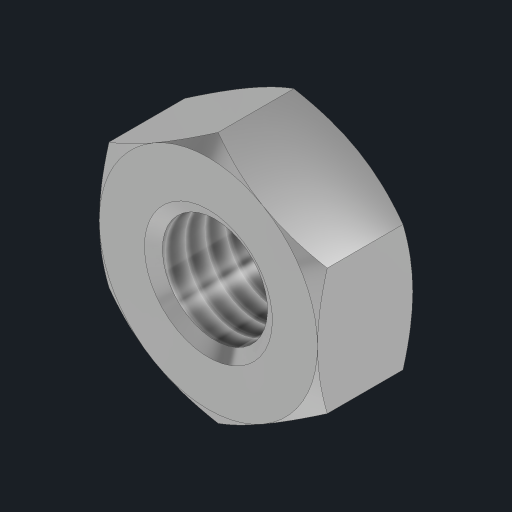
# Autodesk Inventor part: Porca Sextavada DIN 934 - M3 - 8
Saved by Autodesk Inventor 2024.3 (Build 283343000, 343)
## iProperties
Created: 2025-07-13
Part Number: Porca Sextavada DIN 934 - M3 - 8
Material: Aço inoxidável
Document SubType Name: Modeling
Designer: Cliente
Mass: 0.390793 g
Surface Area: 1.02672 cm^2
Volume: 0.0488491 cm^3
Density: 8 g/cm^3
Appearance: Aço inoxidável - Brilhoso
Author: Cliente
Autodesk Inventor part; units mm, degrees
ref_plane "YZ Plane" through (0, 0, 0) normal (1, 0, 0) x (0, 1, 0)
ref_plane "XZ Plane" through (0, 0, 0) normal (0, 1, 0) x (-1, 0, 0)
ref_plane "XY Plane" through (0, 0, 0) normal (0, 0, 1) x (1, 0, 0)
sketch "Esboço1" plane through (0, 0, 0) normal (0, 0, 1) x (1, 0, 0)
  line L0 (0, 3.1754) -> (2.75, 1.5877)
  line L1 (2.75, 1.5877) -> (2.75, -1.5877)
  line L2 (2.75, -1.5877) -> (0, -3.1754)
  line L3 (0, -3.1754) -> (-2.75, -1.5877)
  line L4 (-2.75, -1.5877) -> (-2.75, 1.5877)
  line L5 (-2.75, 1.5877) -> (0, 3.1754)
  circle A0 centre (0, 0) radius 1.325
  dimension "d0" = 5.5
  dimension "d1" = 2.65
  constraints: 12 end point, 2 coincident, 1 centre point, 1 vertical alignment, 13 other
  measures "d0" distance between parallel lines of L1 L4
  measures "d1" diameter of A0
extrude "Extrusão1" add sketch "Esboço1" along normal blind 2.4
sketch "Esboço2" plane through (0, 0, 0) normal (1, 0, 0) x (0, 1, 0)
  line L0 (3.1754, 0) -> (1.5877, 0) projected
  line L1 (1.5877, 0) -> (1.5877, 2.4) projected
  line L2 (3.1754, 2.4) -> (1.5877, 2.4) projected
  line L3 (3.1754, 0) -> (3.1754, 2.4) projected
  line L4 (1.325, 2.4) -> (1.325, 0) projected
  line L5 (0, 0) -> (1.6125, 0)
  line L6 (1.6125, 0) -> (1.325, 0.166)
  line L7 (0, 0) -> (2.75, 0)
  line L8 (2.75, 0) -> (3.1754, 0.2456)
  line L9 (2.75, 0) -> (3.2412, 0) construction
  line L10 (0, -0.64) -> (0, 3.84) projected
  line L11 (0, 1.2) -> (1.325, 1.2)
  line L12 (0, 2.4) -> (1.6125, 2.4)
  line L13 (1.6125, 2.4) -> (1.325, 2.234)
  line L14 (2.75, 2.4) -> (3.1754, 2.1544)
  point P0 (1.5877, 0.0143)
  point P1 (2.75, 2.4)
  point P2 (1.325, 0)
  point P3 (1.5877, 0)
  point P4 (1.5877, 2.3857)
  dimension "d4" = 1.6125
  dimension "d5" = 30
  dimension "d6" = 2.75
  dimension "d7" = 30
  constraints: 18 end point, 5 point on line, 5 symmetric about line, 2 horizontal, 1 equal length, 1 midpoint
  measures "d4" distance of L5.start L5.end
  measures "d5" angle of L6 L5
  measures "d6" distance of L5.start L7.end
  measures "d7" angle of L9 L8
revolve "Revolução1" cut sketch "Esboço2" angle 360 about axis through (0, 0, -10) along (0, 0, 1) contours L0 L8 L3 | L0 L1 L6 | L14 L2 L3 | L5 L4 L6 L1 | L13 L4 L12 L1 | L1 L2 L13
thread "Rosca1" size "M3x0.5" class "6H" standard "ANSI Metric M Profile" full length
